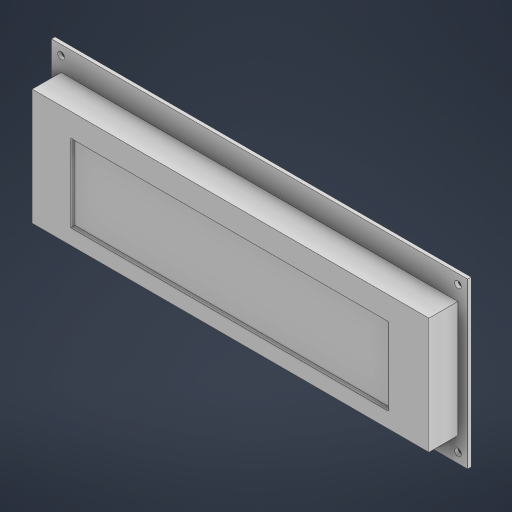
# Autodesk Inventor part: VDF
Saved by Autodesk Inventor 2024.3 (Build 283343000, 343)
## iProperties
Created: 2026-11-11
Part Number: VDF
Material: Generic
Document SubType Name: Modeling
Designer: REMOTE
Density: 1 g/cm^3
Appearance: Default
Author: REMOTE
Autodesk Inventor part; units mm, degrees
ref_plane "YZ Plane" through (0, 0, 0) normal (1, 0, 0) x (0, 1, 0)
ref_plane "XZ Plane" through (0, 0, 0) normal (0, 1, 0) x (-1, 0, 0)
ref_plane "XY Plane" through (0, 0, 0) normal (0, 0, 1) x (1, 0, 0)
sketch "Sketch1" plane through (0, 0, 0) normal (0, 0, 1) x (1, 0, 0)
  line L0 (-107.5, -42.5) -> (107.5, -42.5)
  line L1 (107.5, -42.5) -> (107.5, 42.5)
  line L2 (107.5, 42.5) -> (-107.5, 42.5)
  line L3 (-107.5, 42.5) -> (-107.5, -42.5)
  line L4 (-107.5, -42.5) -> (107.5, 42.5) construction
  line L5 (107.5, -42.5) -> (-107.5, 42.5) construction
  circle A0 centre (-102.5, 37.5) radius 1.75
  circle A1 centre (-102.5, -37.5) radius 1.75
  circle A2 centre (102.5, 37.5) radius 1.75
  circle A3 centre (102.5, -37.5) radius 1.75
  point P0 (0, 0)
  dimension "d0" = 215
  dimension "d1" = 85
  dimension "d2" = 3.5
  dimension "d3" = 5
  dimension "d4" = 5
  dimension "d5" = 3.5
  dimension "d6" = 5
  dimension "d7" = 5
  dimension "d8" = 3.5
  dimension "d9" = 5
  dimension "d10" = 5
  dimension "d11" = 3.5
  dimension "d12" = 5
  dimension "d13" = 5
  constraints: 12 end point, 4 centre point, 2 midpoint, 2 parallel, 1 horizontal, 1 perpendicular
  measures "d0" distance of L2.end L1.end
  measures "d1" distance of L1.end L0.end
  measures "d2" diameter of A0
  measures "d3" distance from line of L2 A0.centre
  measures "d4" distance from line of L3 A0.centre
  measures "d5" diameter of A1
  measures "d6" distance from line of L0 A1.centre
  measures "d7" distance from line of L3 A1.centre
  measures "d8" diameter of A2
  measures "d9" distance from line of L1 A2.centre
  measures "d10" distance from line of L2 A2.centre
  measures "d11" diameter of A3
  measures "d12" distance from line of L0 A3.centre
  measures "d13" distance from line of L1 A3.centre
extrude "Extrusion1" add sketch "Sketch1" along normal blind 1.8
sketch "Sketch2" plane through (0, 0, 1.8) normal (0, 0, 1) x (1, 0, 0)
  line L0 (-102.5, -30) -> (102.5, -30)
  line L1 (102.5, -30) -> (102.5, 30)
  line L2 (102.5, 30) -> (-102.5, 30)
  line L3 (-102.5, 30) -> (-102.5, -30)
  line L4 (-102.5, -30) -> (102.5, 30) construction
  line L5 (102.5, -30) -> (-102.5, 30) construction
  point P0 (0, 0)
  dimension "d16" = 205
  dimension "d17" = 60
  constraints: 12 end point, 2 midpoint, 2 parallel, 1 horizontal, 1 perpendicular
  measures "d16" distance of L2.end L1.end
  measures "d17" distance of L1.end L0.end
extrude "Extrusion2" add sketch "Sketch2" along normal blind 15
sketch "Sketch3" plane through (0, 0, 16.8) normal (0, 0, 1) x (1, 0, 0)
  line L0 (-82.5, -22) -> (81.5, -22)
  line L1 (81.5, -22) -> (81.5, 18)
  line L2 (81.5, 18) -> (-82.5, 18)
  line L3 (-82.5, 18) -> (-82.5, -22)
  line L4 (-102.5, 30) -> (-102.5, -30) projected
  line L5 (-102.5, -30) -> (102.5, -30) projected
  point P0 (0, 0)
  dimension "d20" = 164
  dimension "d21" = 40
  dimension "d22" = 20
  dimension "d23" = 8
  constraints: 8 end point, 2 parallel, 1 horizontal, 1 perpendicular
  measures "d20" distance of L2.end L1.end
  measures "d21" distance of L1.end L0.end
  measures "d22" distance between parallel lines of L4 L3
  measures "d23" distance between parallel lines of L5 L0
extrude "Extrusion3" cut sketch "Sketch3" against normal blind 2
sketch "Sketch4" plane through (0, 0, 0) normal (0, 0, -1) x (-1, 0, 0)
  line L0 (107, 20.25) -> (98.5, 20.25)
  line L1 (98.5, 20.25) -> (98.5, -20.25)
  line L2 (98.5, -20.25) -> (107, -20.25)
  line L3 (107, -20.25) -> (107, 20.25)
  line L4 (107.5, 42.5) -> (107.5, -42.5) projected
  line L5 (107.5, -42.5) -> (-107.5, -42.5) projected
  point P0 (0, 0)
  dimension "d26" = 8.5
  dimension "d27" = 40.5
  dimension "d28" = 0.5
  dimension "d29" = 22.25
  constraints: 8 end point, 2 parallel, 1 horizontal, 1 perpendicular
  measures "d26" distance of L2.end L1.end
  measures "d27" distance of L1.end L0.end
  measures "d28" distance between parallel lines of L4 L3
  measures "d29" distance between parallel lines of L5 L2
extrude "Extrusion4" add sketch "Sketch4" along normal blind 9.5
body "Solid1"
